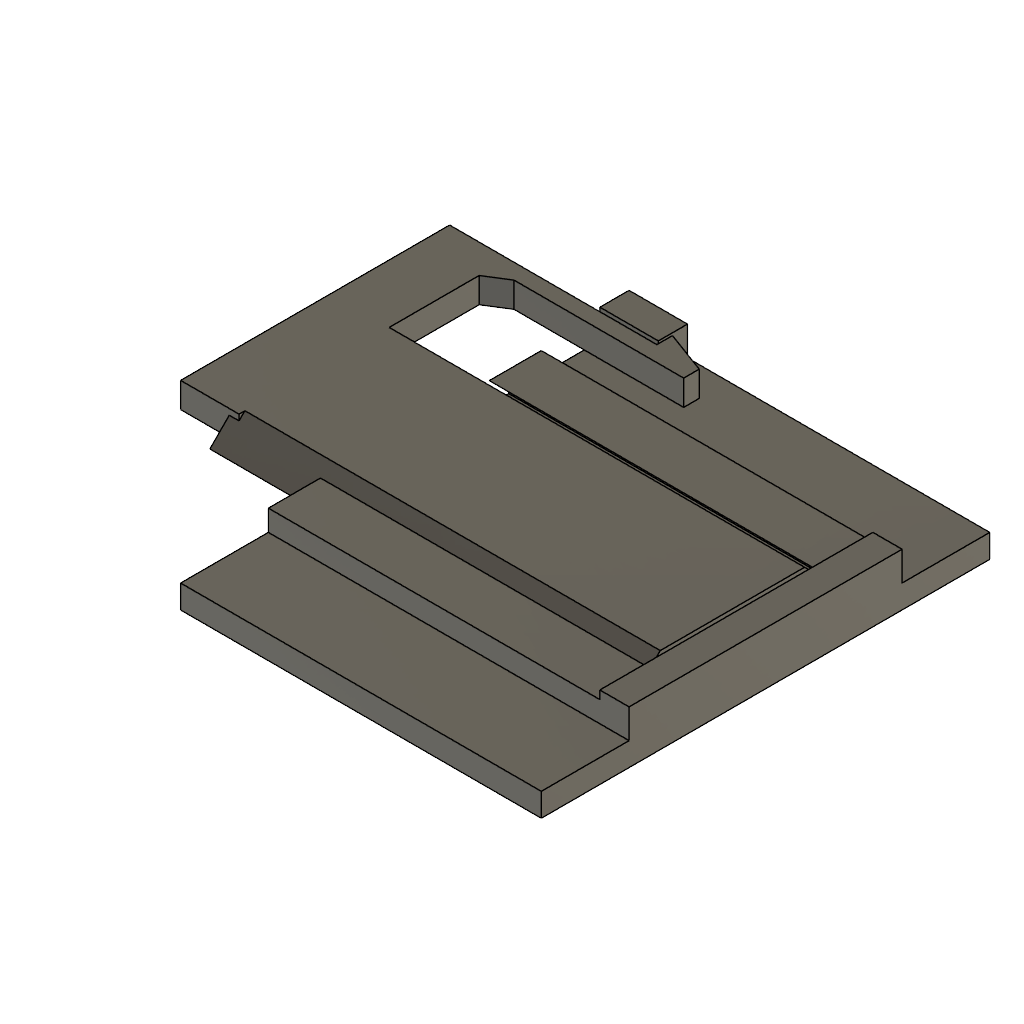
CloudBot-Rail-Latch-Coupon (Autodesk Fusion 360 design; units mm, degrees)
part number: 2026-11-13-20-55-08-535
part number: 2026-11-13-20-55-08-802
part number: 2026-11-13-20-55-09-025
Autodesk Fusion 360 part; units mm, degrees
sketch "草图1" plane through (0, 0, 0) normal (0, 0, 1) x (1, 0, 0) in component "Rail base - entry at open end"
  line L0 (0, -23) -> (37, -23)
  line L1 (37, -23) -> (37, 23)
  line L2 (37, 23) -> (0, 23)
  line L3 (0, 23) -> (0, -23)
extrude "Flat base" add sketch "草图1" along normal blind 2.4 makes body 1 in component "Rail base - entry at open end"
sketch "草图2" plane through (0, 0, 0) normal (1, 0, 0) x (0, 0, -1) in component "Rail base - entry at open end"
  line L0 (-2.2, -10.65) -> (-2.2, -14)
  line L1 (-2.2, -14) -> (-4.55, -14)
  line L2 (-4.55, -14) -> (-4.55, -8.65)
  line L3 (-4.55, -8.65) -> (-2.55, -10.65)
  line L4 (-2.55, -10.65) -> (-2.2, -10.65)
extrude "45 degree left rail" add sketch "草图2" along normal blind 34 bodies 1 in component "Rail base - entry at open end"
sketch "草图3" plane through (0, 0, 0) normal (1, 0, 0) x (0, 0, -1) in component "Rail base - entry at open end"
  line L0 (-2.2, 10.65) -> (-2.2, 14)
  line L1 (-2.2, 14) -> (-4.55, 14)
  line L2 (-4.55, 14) -> (-4.55, 8.65)
  line L3 (-4.55, 8.65) -> (-2.55, 10.65)
  line L4 (-2.55, 10.65) -> (-2.2, 10.65)
extrude "45 degree right rail" add sketch "草图3" along normal blind 34 bodies 1 in component "Rail base - entry at open end"
sketch "草图4" plane through (0, 0, 0) normal (0, 0, 1) x (1, 0, 0) in component "Rail base - entry at open end"
  line L0 (34, -14) -> (37, -14)
  line L1 (37, -14) -> (37, 14)
  line L2 (37, 14) -> (34, 14)
  line L3 (34, 14) -> (34, -14)
extrude "End stop" add sketch "草图4" along normal blind 5.4 bodies 1 in component "Rail base - entry at open end"
sketch "草图5" plane through (0, 0, 0) normal (0, 0, 1) x (1, 0, 0) in component "Rail base - entry at open end"
  line L0 (0, 20) -> (6, 20)
  line L1 (6, 20) -> (6, 23)
  line L2 (6, 23) -> (0, 23)
  line L3 (0, 23) -> (0, 20)
extrude "Latch catch" add sketch "草图5" along normal blind 5.4 bodies 1 in component "Rail base - entry at open end"
ref_plane "工作平面1" through (-10, 0, 0) normal (1, 0, 0) x (0, 1, 0) in component "Slider - press outside tooth inward to release"
sketch "草图1 (2)" plane through (-10, 0, 0) normal (1, 0, 0) x (0, 0, -1) in component "Slider - press outside tooth inward to release"
  line L0 (0, -10) -> (0, 10)
  line L1 (0, 10) -> (-2.6, 7.4)
  line L2 (-2.6, 7.4) -> (-2.6, -7.4)
  line L3 (-2.6, -7.4) -> (0, -10)
extrude "Sliding tongue" add sketch "草图1 (2)" along normal blind 43.6 separate body makes body 2 in component "Slider - press outside tooth inward to release"
sketch "草图2 (2)" plane through (0, 0, 0) normal (0, 0, 1) x (1, 0, 0) in component "Slider - press outside tooth inward to release"
  line L0 (-15, -8) -> (-9, -8)
  line L1 (-9, -8) -> (-9, 19.6)
  line L2 (-9, 19.6) -> (-15, 19.6)
  line L3 (-15, 19.6) -> (-15, -8)
extrude "Pull handle" add sketch "草图2 (2)" along normal blind 2.6 bodies 2 in component "Slider - press outside tooth inward to release"
sketch "草图3 (2)" plane through (0, 0, 0) normal (0, 0, 1) x (1, 0, 0) in component "Slider - press outside tooth inward to release"
  line L0 (-10, 16) -> (-6.8, 18)
  line L1 (-6.8, 18) -> (10.6, 18)
  line L2 (10.6, 18) -> (10.6, 19.6)
  line L3 (10.6, 19.6) -> (6.25, 21.2)
  line L4 (6.25, 21.2) -> (6.25, 19.6)
  line L5 (6.25, 19.6) -> (-10, 19.6)
  line L6 (-10, 19.6) -> (-10, 16)
extrude "Spring arm, insertion ramp and lock shoulder" add sketch "草图3 (2)" along normal blind 2.6 bodies 2 in component "Slider - press outside tooth inward to release"
component "Rail base - entry at open end" placed x (1, 0, 0) y (0, 1, 0) z (0, 0, 1) at (0, 0, 0)
component "Slider - press outside tooth inward to release" placed x (1, 0, 0) y (0, 1, 0) z (0, 0, 1) at (0, 0, 2.8)
